Autodesk Fusion 360 part; units mm, degrees
(part 2 of 3)
sketch "locating_stops" plane through (0, 0, 7.25) normal (0, 0, 1) x (1, 0, 0) in component "drop_plate"
  line L0 (-82.375, -82.375) -> (-75.25, -82.375)
  line L1 (-75.25, -82.375) -> (-75.25, -80.125)
  line L2 (-75.25, -80.125) -> (-82.375, -80.125)
  line L3 (-82.375, -80.125) -> (-82.375, -82.375)
  line L4 (-82.375, -82.375) -> (-80.125, -82.375)
  line L5 (-80.125, -82.375) -> (-80.125, -75.25)
  line L6 (-80.125, -75.25) -> (-82.375, -75.25)
  line L7 (-82.375, -75.25) -> (-82.375, -82.375)
  line L8 (-82.375, -49.875) -> (-75.25, -49.875)
  line L9 (-75.25, -49.875) -> (-75.25, -47.625)
  line L10 (-75.25, -47.625) -> (-82.375, -47.625)
  line L11 (-82.375, -47.625) -> (-82.375, -49.875)
  line L12 (-82.375, -54.75) -> (-80.125, -54.75)
  line L13 (-80.125, -54.75) -> (-80.125, -42.75)
  line L14 (-80.125, -42.75) -> (-82.375, -42.75)
  line L15 (-82.375, -42.75) -> (-82.375, -54.75)
  line L16 (-82.375, -17.375) -> (-75.25, -17.375)
  line L17 (-75.25, -17.375) -> (-75.25, -15.125)
  line L18 (-75.25, -15.125) -> (-82.375, -15.125)
  line L19 (-82.375, -15.125) -> (-82.375, -17.375)
  line L20 (-82.375, -22.25) -> (-80.125, -22.25)
  line L21 (-80.125, -22.25) -> (-80.125, -10.25)
  line L22 (-80.125, -10.25) -> (-82.375, -10.25)
  line L23 (-82.375, -10.25) -> (-82.375, -22.25)
  line L24 (-82.375, 15.125) -> (-75.25, 15.125)
  line L25 (-75.25, 15.125) -> (-75.25, 17.375)
  line L26 (-75.25, 17.375) -> (-82.375, 17.375)
  line L27 (-82.375, 17.375) -> (-82.375, 15.125)
  line L28 (-82.375, 10.25) -> (-80.125, 10.25)
  line L29 (-80.125, 10.25) -> (-80.125, 22.25)
  line L30 (-80.125, 22.25) -> (-82.375, 22.25)
  line L31 (-82.375, 22.25) -> (-82.375, 10.25)
  line L32 (-82.375, 47.625) -> (-75.25, 47.625)
  line L33 (-75.25, 47.625) -> (-75.25, 49.875)
  line L34 (-75.25, 49.875) -> (-82.375, 49.875)
  line L35 (-82.375, 49.875) -> (-82.375, 47.625)
  line L36 (-82.375, 42.75) -> (-80.125, 42.75)
  line L37 (-80.125, 42.75) -> (-80.125, 54.75)
  line L38 (-80.125, 54.75) -> (-82.375, 54.75)
  line L39 (-82.375, 54.75) -> (-82.375, 42.75)
  line L40 (-82.375, 80.125) -> (-75.25, 80.125)
  line L41 (-75.25, 80.125) -> (-75.25, 82.375)
  line L42 (-75.25, 82.375) -> (-82.375, 82.375)
  line L43 (-82.375, 82.375) -> (-82.375, 80.125)
  line L44 (-82.375, 75.25) -> (-80.125, 75.25)
  line L45 (-80.125, 75.25) -> (-80.125, 82.375)
  line L46 (-80.125, 82.375) -> (-82.375, 82.375)
  line L47 (-82.375, 82.375) -> (-82.375, 75.25)
  line L48 (-54.75, -82.375) -> (-42.75, -82.375)
  line L49 (-42.75, -82.375) -> (-42.75, -80.125)
  line L50 (-42.75, -80.125) -> (-54.75, -80.125)
  line L51 (-54.75, -80.125) -> (-54.75, -82.375)
  line L52 (-49.875, -82.375) -> (-47.625, -82.375)
  line L53 (-47.625, -82.375) -> (-47.625, -75.25)
  line L54 (-47.625, -75.25) -> (-49.875, -75.25)
  line L55 (-49.875, -75.25) -> (-49.875, -82.375)
  line L56 (-54.75, -49.875) -> (-42.75, -49.875)
  line L57 (-42.75, -49.875) -> (-42.75, -47.625)
  line L58 (-42.75, -47.625) -> (-54.75, -47.625)
  line L59 (-54.75, -47.625) -> (-54.75, -49.875)
  line L60 (-49.875, -54.75) -> (-47.625, -54.75)
  line L61 (-47.625, -54.75) -> (-47.625, -42.75)
  line L62 (-47.625, -42.75) -> (-49.875, -42.75)
  line L63 (-49.875, -42.75) -> (-49.875, -54.75)
  line L64 (-54.75, -17.375) -> (-42.75, -17.375)
  line L65 (-42.75, -17.375) -> (-42.75, -15.125)
  line L66 (-42.75, -15.125) -> (-54.75, -15.125)
  line L67 (-54.75, -15.125) -> (-54.75, -17.375)
  line L68 (-49.875, -22.25) -> (-47.625, -22.25)
  line L69 (-47.625, -22.25) -> (-47.625, -10.25)
  line L70 (-47.625, -10.25) -> (-49.875, -10.25)
  line L71 (-49.875, -10.25) -> (-49.875, -22.25)
  line L72 (-54.75, 15.125) -> (-42.75, 15.125)
  line L73 (-42.75, 15.125) -> (-42.75, 17.375)
  line L74 (-42.75, 17.375) -> (-54.75, 17.375)
  line L75 (-54.75, 17.375) -> (-54.75, 15.125)
  line L76 (-49.875, 10.25) -> (-47.625, 10.25)
  line L77 (-47.625, 10.25) -> (-47.625, 22.25)
  line L78 (-47.625, 22.25) -> (-49.875, 22.25)
  line L79 (-49.875, 22.25) -> (-49.875, 10.25)
  line L80 (-54.75, 47.625) -> (-42.75, 47.625)
  line L81 (-42.75, 47.625) -> (-42.75, 49.875)
  line L82 (-42.75, 49.875) -> (-54.75, 49.875)
  line L83 (-54.75, 49.875) -> (-54.75, 47.625)
  line L84 (-49.875, 42.75) -> (-47.625, 42.75)
  line L85 (-47.625, 42.75) -> (-47.625, 54.75)
  line L86 (-47.625, 54.75) -> (-49.875, 54.75)
  line L87 (-49.875, 54.75) -> (-49.875, 42.75)
  line L88 (-54.75, 80.125) -> (-42.75, 80.125)
  line L89 (-42.75, 80.125) -> (-42.75, 82.375)
  line L90 (-42.75, 82.375) -> (-54.75, 82.375)
  line L91 (-54.75, 82.375) -> (-54.75, 80.125)
  line L92 (-49.875, 75.25) -> (-47.625, 75.25)
  line L93 (-47.625, 75.25) -> (-47.625, 82.375)
  line L94 (-47.625, 82.375) -> (-49.875, 82.375)
  line L95 (-49.875, 82.375) -> (-49.875, 75.25)
  line L96 (-22.25, -82.375) -> (-10.25, -82.375)
  line L97 (-10.25, -82.375) -> (-10.25, -80.125)
  line L98 (-10.25, -80.125) -> (-22.25, -80.125)
  line L99 (-22.25, -80.125) -> (-22.25, -82.375)
  line L100 (-17.375, -82.375) -> (-15.125, -82.375)
  line L101 (-15.125, -82.375) -> (-15.125, -75.25)
  line L102 (-15.125, -75.25) -> (-17.375, -75.25)
  line L103 (-17.375, -75.25) -> (-17.375, -82.375)
  line L104 (-22.25, -49.875) -> (-10.25, -49.875)
  line L105 (-10.25, -49.875) -> (-10.25, -47.625)
  line L106 (-10.25, -47.625) -> (-22.25, -47.625)
  line L107 (-22.25, -47.625) -> (-22.25, -49.875)
  line L108 (-17.375, -54.75) -> (-15.125, -54.75)
  line L109 (-15.125, -54.75) -> (-15.125, -42.75)
  line L110 (-15.125, -42.75) -> (-17.375, -42.75)
  line L111 (-17.375, -42.75) -> (-17.375, -54.75)
  line L112 (-22.25, -17.375) -> (-10.25, -17.375)
  line L113 (-10.25, -17.375) -> (-10.25, -15.125)
  line L114 (-10.25, -15.125) -> (-22.25, -15.125)
  line L115 (-22.25, -15.125) -> (-22.25, -17.375)
  line L116 (-17.375, -22.25) -> (-15.125, -22.25)
  line L117 (-15.125, -22.25) -> (-15.125, -10.25)
  line L118 (-15.125, -10.25) -> (-17.375, -10.25)
  line L119 (-17.375, -10.25) -> (-17.375, -22.25)
  line L120 (-22.25, 15.125) -> (-10.25, 15.125)
  line L121 (-10.25, 15.125) -> (-10.25, 17.375)
  line L122 (-10.25, 17.375) -> (-22.25, 17.375)
  line L123 (-22.25, 17.375) -> (-22.25, 15.125)
  line L124 (-17.375, 10.25) -> (-15.125, 10.25)
  line L125 (-15.125, 10.25) -> (-15.125, 22.25)
  line L126 (-15.125, 22.25) -> (-17.375, 22.25)
  line L127 (-17.375, 22.25) -> (-17.375, 10.25)
  line L128 (-22.25, 47.625) -> (-10.25, 47.625)
  line L129 (-10.25, 47.625) -> (-10.25, 49.875)
  line L130 (-10.25, 49.875) -> (-22.25, 49.875)
  line L131 (-22.25, 49.875) -> (-22.25, 47.625)
  line L132 (-17.375, 42.75) -> (-15.125, 42.75)
  line L133 (-15.125, 42.75) -> (-15.125, 54.75)
  line L134 (-15.125, 54.75) -> (-17.375, 54.75)
  line L135 (-17.375, 54.75) -> (-17.375, 42.75)
  line L136 (-22.25, 80.125) -> (-10.25, 80.125)
  line L137 (-10.25, 80.125) -> (-10.25, 82.375)
  line L138 (-10.25, 82.375) -> (-22.25, 82.375)
  line L139 (-22.25, 82.375) -> (-22.25, 80.125)
  line L140 (-17.375, 75.25) -> (-15.125, 75.25)
  line L141 (-15.125, 75.25) -> (-15.125, 82.375)
  line L142 (-15.125, 82.375) -> (-17.375, 82.375)
  line L143 (-17.375, 82.375) -> (-17.375, 75.25)
  line L144 (10.25, -82.375) -> (22.25, -82.375)
  line L145 (22.25, -82.375) -> (22.25, -80.125)
  line L146 (22.25, -80.125) -> (10.25, -80.125)
  line L147 (10.25, -80.125) -> (10.25, -82.375)
  line L148 (15.125, -82.375) -> (17.375, -82.375)
  line L149 (17.375, -82.375) -> (17.375, -75.25)
  line L150 (17.375, -75.25) -> (15.125, -75.25)
  line L151 (15.125, -75.25) -> (15.125, -82.375)
  line L152 (10.25, -49.875) -> (22.25, -49.875)
  line L153 (22.25, -49.875) -> (22.25, -47.625)
  line L154 (22.25, -47.625) -> (10.25, -47.625)
  line L155 (10.25, -47.625) -> (10.25, -49.875)
  line L156 (15.125, -54.75) -> (17.375, -54.75)
  line L157 (17.375, -54.75) -> (17.375, -42.75)
  line L158 (17.375, -42.75) -> (15.125, -42.75)
  line L159 (15.125, -42.75) -> (15.125, -54.75)
  line L160 (10.25, -17.375) -> (22.25, -17.375)
  line L161 (22.25, -17.375) -> (22.25, -15.125)
  line L162 (22.25, -15.125) -> (10.25, -15.125)
  line L163 (10.25, -15.125) -> (10.25, -17.375)
  line L164 (15.125, -22.25) -> (17.375, -22.25)
  line L165 (17.375, -22.25) -> (17.375, -10.25)
  line L166 (17.375, -10.25) -> (15.125, -10.25)
  line L167 (15.125, -10.25) -> (15.125, -22.25)
  line L168 (10.25, 15.125) -> (22.25, 15.125)
  line L169 (22.25, 15.125) -> (22.25, 17.375)
  line L170 (22.25, 17.375) -> (10.25, 17.375)
  line L171 (10.25, 17.375) -> (10.25, 15.125)
  line L172 (15.125, 10.25) -> (17.375, 10.25)
  line L173 (17.375, 10.25) -> (17.375, 22.25)
  line L174 (17.375, 22.25) -> (15.125, 22.25)
  line L175 (15.125, 22.25) -> (15.125, 10.25)
  line L176 (10.25, 47.625) -> (22.25, 47.625)
  line L177 (22.25, 47.625) -> (22.25, 49.875)
  line L178 (22.25, 49.875) -> (10.25, 49.875)
  line L179 (10.25, 49.875) -> (10.25, 47.625)
  line L180 (15.125, 42.75) -> (17.375, 42.75)
  line L181 (17.375, 42.75) -> (17.375, 54.75)
  line L182 (17.375, 54.75) -> (15.125, 54.75)
  line L183 (15.125, 54.75) -> (15.125, 42.75)
  line L184 (10.25, 80.125) -> (22.25, 80.125)
  line L185 (22.25, 80.125) -> (22.25, 82.375)
  line L186 (22.25, 82.375) -> (10.25, 82.375)
  line L187 (10.25, 82.375) -> (10.25, 80.125)
  line L188 (15.125, 75.25) -> (17.375, 75.25)
  line L189 (17.375, 75.25) -> (17.375, 82.375)
  line L190 (17.375, 82.375) -> (15.125, 82.375)
  line L191 (15.125, 82.375) -> (15.125, 75.25)
  line L192 (42.75, -82.375) -> (54.75, -82.375)
  line L193 (54.75, -82.375) -> (54.75, -80.125)
  line L194 (54.75, -80.125) -> (42.75, -80.125)
  line L195 (42.75, -80.125) -> (42.75, -82.375)
  line L196 (47.625, -82.375) -> (49.875, -82.375)
  line L197 (49.875, -82.375) -> (49.875, -75.25)
  line L198 (49.875, -75.25) -> (47.625, -75.25)
  line L199 (47.625, -75.25) -> (47.625, -82.375)
  line L200 (42.75, -49.875) -> (54.75, -49.875)
  line L201 (54.75, -49.875) -> (54.75, -47.625)
  line L202 (54.75, -47.625) -> (42.75, -47.625)
  line L203 (42.75, -47.625) -> (42.75, -49.875)
  line L204 (47.625, -54.75) -> (49.875, -54.75)
  line L205 (49.875, -54.75) -> (49.875, -42.75)
  line L206 (49.875, -42.75) -> (47.625, -42.75)
  line L207 (47.625, -42.75) -> (47.625, -54.75)
  line L208 (42.75, -17.375) -> (54.75, -17.375)
  line L209 (54.75, -17.375) -> (54.75, -15.125)
  line L210 (54.75, -15.125) -> (42.75, -15.125)
  line L211 (42.75, -15.125) -> (42.75, -17.375)
  line L212 (47.625, -22.25) -> (49.875, -22.25)
  line L213 (49.875, -22.25) -> (49.875, -10.25)
  line L214 (49.875, -10.25) -> (47.625, -10.25)
  line L215 (47.625, -10.25) -> (47.625, -22.25)
  line L216 (42.75, 15.125) -> (54.75, 15.125)
  line L217 (54.75, 15.125) -> (54.75, 17.375)
  line L218 (54.75, 17.375) -> (42.75, 17.375)
  line L219 (42.75, 17.375) -> (42.75, 15.125)
  line L220 (47.625, 10.25) -> (49.875, 10.25)
  line L221 (49.875, 10.25) -> (49.875, 22.25)
  line L222 (49.875, 22.25) -> (47.625, 22.25)
  line L223 (47.625, 22.25) -> (47.625, 10.25)
  line L224 (42.75, 47.625) -> (54.75, 47.625)
  line L225 (54.75, 47.625) -> (54.75, 49.875)
  line L226 (54.75, 49.875) -> (42.75, 49.875)
  line L227 (42.75, 49.875) -> (42.75, 47.625)
  line L228 (47.625, 42.75) -> (49.875, 42.75)
  line L229 (49.875, 42.75) -> (49.875, 54.75)
  line L230 (49.875, 54.75) -> (47.625, 54.75)
  line L231 (47.625, 54.75) -> (47.625, 42.75)
  line L232 (42.75, 80.125) -> (54.75, 80.125)
  line L233 (54.75, 80.125) -> (54.75, 82.375)
  line L234 (54.75, 82.375) -> (42.75, 82.375)
  line L235 (42.75, 82.375) -> (42.75, 80.125)
  line L236 (47.625, 75.25) -> (49.875, 75.25)
  line L237 (49.875, 75.25) -> (49.875, 82.375)
  line L238 (49.875, 82.375) -> (47.625, 82.375)
  line L239 (47.625, 82.375) -> (47.625, 75.25)
  line L240 (75.25, -82.375) -> (82.375, -82.375)
  line L241 (82.375, -82.375) -> (82.375, -80.125)
  line L242 (82.375, -80.125) -> (75.25, -80.125)
  line L243 (75.25, -80.125) -> (75.25, -82.375)
  line L244 (80.125, -82.375) -> (82.375, -82.375)
  line L245 (82.375, -82.375) -> (82.375, -75.25)
  line L246 (82.375, -75.25) -> (80.125, -75.25)
  line L247 (80.125, -75.25) -> (80.125, -82.375)
  line L248 (75.25, -49.875) -> (82.375, -49.875)
  line L249 (82.375, -49.875) -> (82.375, -47.625)
  line L250 (82.375, -47.625) -> (75.25, -47.625)
  line L251 (75.25, -47.625) -> (75.25, -49.875)
  line L252 (80.125, -54.75) -> (82.375, -54.75)
  line L253 (82.375, -54.75) -> (82.375, -42.75)
  line L254 (82.375, -42.75) -> (80.125, -42.75)
  line L255 (80.125, -42.75) -> (80.125, -54.75)
  line L256 (75.25, -17.375) -> (82.375, -17.375)
  line L257 (82.375, -17.375) -> (82.375, -15.125)
  line L258 (82.375, -15.125) -> (75.25, -15.125)
  line L259 (75.25, -15.125) -> (75.25, -17.375)
  line L260 (80.125, -22.25) -> (82.375, -22.25)
  line L261 (82.375, -22.25) -> (82.375, -10.25)
  line L262 (82.375, -10.25) -> (80.125, -10.25)
  line L263 (80.125, -10.25) -> (80.125, -22.25)
  line L264 (75.25, 15.125) -> (82.375, 15.125)
  line L265 (82.375, 15.125) -> (82.375, 17.375)
  line L266 (82.375, 17.375) -> (75.25, 17.375)
  line L267 (75.25, 17.375) -> (75.25, 15.125)
  line L268 (80.125, 10.25) -> (82.375, 10.25)
  line L269 (82.375, 10.25) -> (82.375, 22.25)
  line L270 (82.375, 22.25) -> (80.125, 22.25)
  line L271 (80.125, 22.25) -> (80.125, 10.25)
  line L272 (75.25, 47.625) -> (82.375, 47.625)
  line L273 (82.375, 47.625) -> (82.375, 49.875)
  line L274 (82.375, 49.875) -> (75.25, 49.875)
  line L275 (75.25, 49.875) -> (75.25, 47.625)
  line L276 (80.125, 42.75) -> (82.375, 42.75)
  line L277 (82.375, 42.75) -> (82.375, 54.75)
  line L278 (82.375, 54.75) -> (80.125, 54.75)
  line L279 (80.125, 54.75) -> (80.125, 42.75)
  line L280 (75.25, 80.125) -> (82.375, 80.125)
  line L281 (82.375, 80.125) -> (82.375, 82.375)
  line L282 (82.375, 82.375) -> (75.25, 82.375)
  line L283 (75.25, 82.375) -> (75.25, 80.125)
  line L284 (80.125, 75.25) -> (82.375, 75.25)
  line L285 (82.375, 75.25) -> (82.375, 82.375)
  line L286 (82.375, 82.375) -> (80.125, 82.375)
  line L287 (80.125, 82.375) -> (80.125, 75.25)
extrude "locating_stops (1)" add sketch "locating_stops" along normal blind 2.4 in component "drop_plate"
ref_plane "WorkPlane7" through (0, 0, 9.65) normal (0, 0, 1) x (1, 0, 0) in component "drop_plate"
sketch "orientation_post" plane through (0, 0, 9.65) normal (0, 0, 1) x (1, 0, 0) in component "drop_plate"
  line L0 (-82.375, -82.375) -> (-80.125, -82.375)
  line L1 (-80.125, -82.375) -> (-80.125, -80.125)
  line L2 (-80.125, -80.125) -> (-82.375, -80.125)
  line L3 (-82.375, -80.125) -> (-82.375, -82.375)
extrude "orientation_post (1)" add sketch "orientation_post" along normal blind 3 in component "drop_plate"
ref_plane "WorkPlane8" through (0, 0, 7.25) normal (0, 0, 1) x (1, 0, 0) in component "drop_plate"
sketch "scale_crosses" plane through (0, 0, 7.25) normal (0, 0, 1) x (1, 0, 0) in component "drop_plate"
  line L0 (-78, -76.3) -> (-74, -76.3)
  line L1 (-74, -76.3) -> (-74, -75.7)
  line L2 (-74, -75.7) -> (-78, -75.7)
  line L3 (-78, -75.7) -> (-78, -76.3)
  line L4 (-76.3, -78) -> (-75.7, -78)
  line L5 (-75.7, -78) -> (-75.7, -74)
  line L6 (-75.7, -74) -> (-76.3, -74)
  line L7 (-76.3, -74) -> (-76.3, -78)
  line L8 (-78, -54.3) -> (-74, -54.3)
  line L9 (-74, -54.3) -> (-74, -53.7)
  line L10 (-74, -53.7) -> (-78, -53.7)
  line L11 (-78, -53.7) -> (-78, -54.3)
  line L12 (-76.3, -56) -> (-75.7, -56)
  line L13 (-75.7, -56) -> (-75.7, -52)
  line L14 (-75.7, -52) -> (-76.3, -52)
  line L15 (-76.3, -52) -> (-76.3, -56)
  line L16 (-56, -76.3) -> (-52, -76.3)
  line L17 (-52, -76.3) -> (-52, -75.7)
  line L18 (-52, -75.7) -> (-56, -75.7)
  line L19 (-56, -75.7) -> (-56, -76.3)
  line L20 (-54.3, -78) -> (-53.7, -78)
  line L21 (-53.7, -78) -> (-53.7, -74)
  line L22 (-53.7, -74) -> (-54.3, -74)
  line L23 (-54.3, -74) -> (-54.3, -78)
  line L24 (-56, -54.3) -> (-52, -54.3)
  line L25 (-52, -54.3) -> (-52, -53.7)
  line L26 (-52, -53.7) -> (-56, -53.7)
  line L27 (-56, -53.7) -> (-56, -54.3)
  line L28 (-54.3, -56) -> (-53.7, -56)
  line L29 (-53.7, -56) -> (-53.7, -52)
  line L30 (-53.7, -52) -> (-54.3, -52)
  line L31 (-54.3, -52) -> (-54.3, -56)
  line L32 (-78, -43.8) -> (-74, -43.8)
  line L33 (-74, -43.8) -> (-74, -43.2)
  line L34 (-74, -43.2) -> (-78, -43.2)
  line L35 (-78, -43.2) -> (-78, -43.8)
  line L36 (-76.3, -45.5) -> (-75.7, -45.5)
  line L37 (-75.7, -45.5) -> (-75.7, -41.5)
  line L38 (-75.7, -41.5) -> (-76.3, -41.5)
  line L39 (-76.3, -41.5) -> (-76.3, -45.5)
  line L40 (-78, -21.8) -> (-74, -21.8)
  line L41 (-74, -21.8) -> (-74, -21.2)
  line L42 (-74, -21.2) -> (-78, -21.2)
  line L43 (-78, -21.2) -> (-78, -21.8)
  line L44 (-76.3, -23.5) -> (-75.7, -23.5)
  line L45 (-75.7, -23.5) -> (-75.7, -19.5)
  line L46 (-75.7, -19.5) -> (-76.3, -19.5)
  line L47 (-76.3, -19.5) -> (-76.3, -23.5)
  line L48 (-56, -43.8) -> (-52, -43.8)
  line L49 (-52, -43.8) -> (-52, -43.2)
  line L50 (-52, -43.2) -> (-56, -43.2)
  line L51 (-56, -43.2) -> (-56, -43.8)
  line L52 (-54.3, -45.5) -> (-53.7, -45.5)
  line L53 (-53.7, -45.5) -> (-53.7, -41.5)
  line L54 (-53.7, -41.5) -> (-54.3, -41.5)
  line L55 (-54.3, -41.5) -> (-54.3, -45.5)
  line L56 (-56, -21.8) -> (-52, -21.8)
  line L57 (-52, -21.8) -> (-52, -21.2)
  line L58 (-52, -21.2) -> (-56, -21.2)
  line L59 (-56, -21.2) -> (-56, -21.8)
  line L60 (-54.3, -23.5) -> (-53.7, -23.5)
  line L61 (-53.7, -23.5) -> (-53.7, -19.5)
  line L62 (-53.7, -19.5) -> (-54.3, -19.5)
  line L63 (-54.3, -19.5) -> (-54.3, -23.5)
  line L64 (-78, -11.3) -> (-74, -11.3)
  line L65 (-74, -11.3) -> (-74, -10.7)
  line L66 (-74, -10.7) -> (-78, -10.7)
  line L67 (-78, -10.7) -> (-78, -11.3)
  line L68 (-76.3, -13) -> (-75.7, -13)
  line L69 (-75.7, -13) -> (-75.7, -9)
  line L70 (-75.7, -9) -> (-76.3, -9)
  line L71 (-76.3, -9) -> (-76.3, -13)
  line L72 (-78, 10.7) -> (-74, 10.7)
  line L73 (-74, 10.7) -> (-74, 11.3)
  line L74 (-74, 11.3) -> (-78, 11.3)
  line L75 (-78, 11.3) -> (-78, 10.7)
  line L76 (-76.3, 9) -> (-75.7, 9)
  line L77 (-75.7, 9) -> (-75.7, 13)
  line L78 (-75.7, 13) -> (-76.3, 13)
  line L79 (-76.3, 13) -> (-76.3, 9)
  line L80 (-56, -11.3) -> (-52, -11.3)
  line L81 (-52, -11.3) -> (-52, -10.7)
  line L82 (-52, -10.7) -> (-56, -10.7)
  line L83 (-56, -10.7) -> (-56, -11.3)
  line L84 (-54.3, -13) -> (-53.7, -13)
  line L85 (-53.7, -13) -> (-53.7, -9)
  line L86 (-53.7, -9) -> (-54.3, -9)
  line L87 (-54.3, -9) -> (-54.3, -13)
  line L88 (-56, 10.7) -> (-52, 10.7)
  line L89 (-52, 10.7) -> (-52, 11.3)
  line L90 (-52, 11.3) -> (-56, 11.3)
  line L91 (-56, 11.3) -> (-56, 10.7)
  line L92 (-54.3, 9) -> (-53.7, 9)
  line L93 (-53.7, 9) -> (-53.7, 13)
  line L94 (-53.7, 13) -> (-54.3, 13)
  line L95 (-54.3, 13) -> (-54.3, 9)
  line L96 (-78, 21.2) -> (-74, 21.2)
  line L97 (-74, 21.2) -> (-74, 21.8)
  line L98 (-74, 21.8) -> (-78, 21.8)
  line L99 (-78, 21.8) -> (-78, 21.2)
  line L100 (-76.3, 19.5) -> (-75.7, 19.5)
  line L101 (-75.7, 19.5) -> (-75.7, 23.5)
  line L102 (-75.7, 23.5) -> (-76.3, 23.5)
  line L103 (-76.3, 23.5) -> (-76.3, 19.5)
  line L104 (-78, 43.2) -> (-74, 43.2)
  line L105 (-74, 43.2) -> (-74, 43.8)
  line L106 (-74, 43.8) -> (-78, 43.8)
  line L107 (-78, 43.8) -> (-78, 43.2)
  line L108 (-76.3, 41.5) -> (-75.7, 41.5)
  line L109 (-75.7, 41.5) -> (-75.7, 45.5)
  line L110 (-75.7, 45.5) -> (-76.3, 45.5)
  line L111 (-76.3, 45.5) -> (-76.3, 41.5)
  line L112 (-56, 21.2) -> (-52, 21.2)
  line L113 (-52, 21.2) -> (-52, 21.8)
  line L114 (-52, 21.8) -> (-56, 21.8)
  line L115 (-56, 21.8) -> (-56, 21.2)
  line L116 (-54.3, 19.5) -> (-53.7, 19.5)
  line L117 (-53.7, 19.5) -> (-53.7, 23.5)
  line L118 (-53.7, 23.5) -> (-54.3, 23.5)
  line L119 (-54.3, 23.5) -> (-54.3, 19.5)
  line L120 (-56, 43.2) -> (-52, 43.2)
  line L121 (-52, 43.2) -> (-52, 43.8)
  line L122 (-52, 43.8) -> (-56, 43.8)
  line L123 (-56, 43.8) -> (-56, 43.2)
  line L124 (-54.3, 41.5) -> (-53.7, 41.5)
  line L125 (-53.7, 41.5) -> (-53.7, 45.5)
  line L126 (-53.7, 45.5) -> (-54.3, 45.5)
  line L127 (-54.3, 45.5) -> (-54.3, 41.5)
  line L128 (-78, 53.7) -> (-74, 53.7)
  line L129 (-74, 53.7) -> (-74, 54.3)
  line L130 (-74, 54.3) -> (-78, 54.3)
  line L131 (-78, 54.3) -> (-78, 53.7)
  line L132 (-76.3, 52) -> (-75.7, 52)
  line L133 (-75.7, 52) -> (-75.7, 56)
  line L134 (-75.7, 56) -> (-76.3, 56)
  line L135 (-76.3, 56) -> (-76.3, 52)
  line L136 (-78, 75.7) -> (-74, 75.7)
  line L137 (-74, 75.7) -> (-74, 76.3)
  line L138 (-74, 76.3) -> (-78, 76.3)
  line L139 (-78, 76.3) -> (-78, 75.7)
  line L140 (-76.3, 74) -> (-75.7, 74)
  line L141 (-75.7, 74) -> (-75.7, 78)
  line L142 (-75.7, 78) -> (-76.3, 78)
  line L143 (-76.3, 78) -> (-76.3, 74)
  line L144 (-56, 53.7) -> (-52, 53.7)
  line L145 (-52, 53.7) -> (-52, 54.3)
  line L146 (-52, 54.3) -> (-56, 54.3)
  line L147 (-56, 54.3) -> (-56, 53.7)
  line L148 (-54.3, 52) -> (-53.7, 52)
  line L149 (-53.7, 52) -> (-53.7, 56)
  line L150 (-53.7, 56) -> (-54.3, 56)
  line L151 (-54.3, 56) -> (-54.3, 52)
  line L152 (-56, 75.7) -> (-52, 75.7)
  line L153 (-52, 75.7) -> (-52, 76.3)
  line L154 (-52, 76.3) -> (-56, 76.3)
  line L155 (-56, 76.3) -> (-56, 75.7)
  line L156 (-54.3, 74) -> (-53.7, 74)
  line L157 (-53.7, 74) -> (-53.7, 78)
  line L158 (-53.7, 78) -> (-54.3, 78)
  line L159 (-54.3, 78) -> (-54.3, 74)
  line L160 (-45.5, -76.3) -> (-41.5, -76.3)
  line L161 (-41.5, -76.3) -> (-41.5, -75.7)
  line L162 (-41.5, -75.7) -> (-45.5, -75.7)
  line L163 (-45.5, -75.7) -> (-45.5, -76.3)
  line L164 (-43.8, -78) -> (-43.2, -78)
  line L165 (-43.2, -78) -> (-43.2, -74)
  line L166 (-43.2, -74) -> (-43.8, -74)
  line L167 (-43.8, -74) -> (-43.8, -78)
  line L168 (-45.5, -54.3) -> (-41.5, -54.3)
  line L169 (-41.5, -54.3) -> (-41.5, -53.7)
  line L170 (-41.5, -53.7) -> (-45.5, -53.7)
  line L171 (-45.5, -53.7) -> (-45.5, -54.3)
  line L172 (-43.8, -56) -> (-43.2, -56)
  line L173 (-43.2, -56) -> (-43.2, -52)
  line L174 (-43.2, -52) -> (-43.8, -52)
  line L175 (-43.8, -52) -> (-43.8, -56)
  line L176 (-23.5, -76.3) -> (-19.5, -76.3)
  line L177 (-19.5, -76.3) -> (-19.5, -75.7)
  line L178 (-19.5, -75.7) -> (-23.5, -75.7)
  line L179 (-23.5, -75.7) -> (-23.5, -76.3)
  line L180 (-21.8, -78) -> (-21.2, -78)
  line L181 (-21.2, -78) -> (-21.2, -74)
  line L182 (-21.2, -74) -> (-21.8, -74)
  line L183 (-21.8, -74) -> (-21.8, -78)
  line L184 (-23.5, -54.3) -> (-19.5, -54.3)
  line L185 (-19.5, -54.3) -> (-19.5, -53.7)
  line L186 (-19.5, -53.7) -> (-23.5, -53.7)
  line L187 (-23.5, -53.7) -> (-23.5, -54.3)
  line L188 (-21.8, -56) -> (-21.2, -56)
  line L189 (-21.2, -56) -> (-21.2, -52)
  line L190 (-21.2, -52) -> (-21.8, -52)
  line L191 (-21.8, -52) -> (-21.8, -56)
  line L192 (-45.5, -43.8) -> (-41.5, -43.8)
  line L193 (-41.5, -43.8) -> (-41.5, -43.2)
  line L194 (-41.5, -43.2) -> (-45.5, -43.2)
  line L195 (-45.5, -43.2) -> (-45.5, -43.8)
  line L196 (-43.8, -45.5) -> (-43.2, -45.5)
  line L197 (-43.2, -45.5) -> (-43.2, -41.5)
  line L198 (-43.2, -41.5) -> (-43.8, -41.5)
  line L199 (-43.8, -41.5) -> (-43.8, -45.5)
  line L200 (-45.5, -21.8) -> (-41.5, -21.8)
  line L201 (-41.5, -21.8) -> (-41.5, -21.2)
  line L202 (-41.5, -21.2) -> (-45.5, -21.2)
  line L203 (-45.5, -21.2) -> (-45.5, -21.8)
  line L204 (-43.8, -23.5) -> (-43.2, -23.5)
  line L205 (-43.2, -23.5) -> (-43.2, -19.5)
  line L206 (-43.2, -19.5) -> (-43.8, -19.5)
  line L207 (-43.8, -19.5) -> (-43.8, -23.5)
  line L208 (-23.5, -43.8) -> (-19.5, -43.8)
  line L209 (-19.5, -43.8) -> (-19.5, -43.2)
  line L210 (-19.5, -43.2) -> (-23.5, -43.2)
  line L211 (-23.5, -43.2) -> (-23.5, -43.8)
  line L212 (-21.8, -45.5) -> (-21.2, -45.5)
  line L213 (-21.2, -45.5) -> (-21.2, -41.5)
  line L214 (-21.2, -41.5) -> (-21.8, -41.5)
  line L215 (-21.8, -41.5) -> (-21.8, -45.5)
  line L216 (-23.5, -21.8) -> (-19.5, -21.8)
  line L217 (-19.5, -21.8) -> (-19.5, -21.2)
  line L218 (-19.5, -21.2) -> (-23.5, -21.2)
  line L219 (-23.5, -21.2) -> (-23.5, -21.8)
  line L220 (-21.8, -23.5) -> (-21.2, -23.5)
  line L221 (-21.2, -23.5) -> (-21.2, -19.5)
  line L222 (-21.2, -19.5) -> (-21.8, -19.5)
  line L223 (-21.8, -19.5) -> (-21.8, -23.5)
  line L224 (-45.5, -11.3) -> (-41.5, -11.3)
  line L225 (-41.5, -11.3) -> (-41.5, -10.7)
  line L226 (-41.5, -10.7) -> (-45.5, -10.7)
  line L227 (-45.5, -10.7) -> (-45.5, -11.3)
  line L228 (-43.8, -13) -> (-43.2, -13)
  line L229 (-43.2, -13) -> (-43.2, -9)
  line L230 (-43.2, -9) -> (-43.8, -9)
  line L231 (-43.8, -9) -> (-43.8, -13)
  line L232 (-45.5, 10.7) -> (-41.5, 10.7)
  line L233 (-41.5, 10.7) -> (-41.5, 11.3)
  line L234 (-41.5, 11.3) -> (-45.5, 11.3)
  line L235 (-45.5, 11.3) -> (-45.5, 10.7)
  line L236 (-43.8, 9) -> (-43.2, 9)
  line L237 (-43.2, 9) -> (-43.2, 13)
  line L238 (-43.2, 13) -> (-43.8, 13)
  line L239 (-43.8, 13) -> (-43.8, 9)
  line L240 (-23.5, -11.3) -> (-19.5, -11.3)
  line L241 (-19.5, -11.3) -> (-19.5, -10.7)
  line L242 (-19.5, -10.7) -> (-23.5, -10.7)
  line L243 (-23.5, -10.7) -> (-23.5, -11.3)
  line L244 (-21.8, -13) -> (-21.2, -13)
  line L245 (-21.2, -13) -> (-21.2, -9)
  line L246 (-21.2, -9) -> (-21.8, -9)
  line L247 (-21.8, -9) -> (-21.8, -13)
  line L248 (-23.5, 10.7) -> (-19.5, 10.7)
  line L249 (-19.5, 10.7) -> (-19.5, 11.3)
  line L250 (-19.5, 11.3) -> (-23.5, 11.3)
  line L251 (-23.5, 11.3) -> (-23.5, 10.7)
  line L252 (-21.8, 9) -> (-21.2, 9)
  line L253 (-21.2, 9) -> (-21.2, 13)
  line L254 (-21.2, 13) -> (-21.8, 13)
  line L255 (-21.8, 13) -> (-21.8, 9)
  line L256 (-45.5, 21.2) -> (-41.5, 21.2)
  line L257 (-41.5, 21.2) -> (-41.5, 21.8)
  line L258 (-41.5, 21.8) -> (-45.5, 21.8)
  line L259 (-45.5, 21.8) -> (-45.5, 21.2)
  line L260 (-43.8, 19.5) -> (-43.2, 19.5)
  line L261 (-43.2, 19.5) -> (-43.2, 23.5)
  line L262 (-43.2, 23.5) -> (-43.8, 23.5)
  line L263 (-43.8, 23.5) -> (-43.8, 19.5)
  line L264 (-45.5, 43.2) -> (-41.5, 43.2)
  line L265 (-41.5, 43.2) -> (-41.5, 43.8)
  line L266 (-41.5, 43.8) -> (-45.5, 43.8)
  line L267 (-45.5, 43.8) -> (-45.5, 43.2)
  line L268 (-43.8, 41.5) -> (-43.2, 41.5)
  line L269 (-43.2, 41.5) -> (-43.2, 45.5)
  line L270 (-43.2, 45.5) -> (-43.8, 45.5)
  line L271 (-43.8, 45.5) -> (-43.8, 41.5)
  line L272 (-23.5, 21.2) -> (-19.5, 21.2)
  line L273 (-19.5, 21.2) -> (-19.5, 21.8)
  line L274 (-19.5, 21.8) -> (-23.5, 21.8)
  line L275 (-23.5, 21.8) -> (-23.5, 21.2)
  line L276 (-21.8, 19.5) -> (-21.2, 19.5)
  line L277 (-21.2, 19.5) -> (-21.2, 23.5)
  line L278 (-21.2, 23.5) -> (-21.8, 23.5)
  line L279 (-21.8, 23.5) -> (-21.8, 19.5)
  line L280 (-23.5, 43.2) -> (-19.5, 43.2)
  line L281 (-19.5, 43.2) -> (-19.5, 43.8)
  line L282 (-19.5, 43.8) -> (-23.5, 43.8)
  line L283 (-23.5, 43.8) -> (-23.5, 43.2)
  line L284 (-21.8, 41.5) -> (-21.2, 41.5)
  line L285 (-21.2, 41.5) -> (-21.2, 45.5)
  line L286 (-21.2, 45.5) -> (-21.8, 45.5)
  line L287 (-21.8, 45.5) -> (-21.8, 41.5)
  line L288 (-45.5, 53.7) -> (-41.5, 53.7)
  line L289 (-41.5, 53.7) -> (-41.5, 54.3)
  line L290 (-41.5, 54.3) -> (-45.5, 54.3)
  line L291 (-45.5, 54.3) -> (-45.5, 53.7)
  line L292 (-43.8, 52) -> (-43.2, 52)
  line L293 (-43.2, 52) -> (-43.2, 56)
  line L294 (-43.2, 56) -> (-43.8, 56)
  line L295 (-43.8, 56) -> (-43.8, 52)
  line L296 (-45.5, 75.7) -> (-41.5, 75.7)
  line L297 (-41.5, 75.7) -> (-41.5, 76.3)
  line L298 (-41.5, 76.3) -> (-45.5, 76.3)
  line L299 (-45.5, 76.3) -> (-45.5, 75.7)
  line L300 (-43.8, 74) -> (-43.2, 74)
  line L301 (-43.2, 74) -> (-43.2, 78)
  line L302 (-43.2, 78) -> (-43.8, 78)
  line L303 (-43.8, 78) -> (-43.8, 74)
  line L304 (-23.5, 53.7) -> (-19.5, 53.7)
  line L305 (-19.5, 53.7) -> (-19.5, 54.3)
  line L306 (-19.5, 54.3) -> (-23.5, 54.3)
  line L307 (-23.5, 54.3) -> (-23.5, 53.7)
  line L308 (-21.8, 52) -> (-21.2, 52)
  line L309 (-21.2, 52) -> (-21.2, 56)
  line L310 (-21.2, 56) -> (-21.8, 56)
  line L311 (-21.8, 56) -> (-21.8, 52)
  line L312 (-23.5, 75.7) -> (-19.5, 75.7)
  line L313 (-19.5, 75.7) -> (-19.5, 76.3)
  line L314 (-19.5, 76.3) -> (-23.5, 76.3)
  line L315 (-23.5, 76.3) -> (-23.5, 75.7)
  line L316 (-21.8, 74) -> (-21.2, 74)
  line L317 (-21.2, 74) -> (-21.2, 78)
  line L318 (-21.2, 78) -> (-21.8, 78)
  line L319 (-21.8, 78) -> (-21.8, 74)
  line L320 (-13, -76.3) -> (-9, -76.3)
  line L321 (-9, -76.3) -> (-9, -75.7)
  line L322 (-9, -75.7) -> (-13, -75.7)
  line L323 (-13, -75.7) -> (-13, -76.3)
  line L324 (-11.3, -78) -> (-10.7, -78)
  line L325 (-10.7, -78) -> (-10.7, -74)
  line L326 (-10.7, -74) -> (-11.3, -74)
  line L327 (-11.3, -74) -> (-11.3, -78)
  line L328 (-13, -54.3) -> (-9, -54.3)
  line L329 (-9, -54.3) -> (-9, -53.7)
  line L330 (-9, -53.7) -> (-13, -53.7)
  line L331 (-13, -53.7) -> (-13, -54.3)
  line L332 (-11.3, -56) -> (-10.7, -56)
  line L333 (-10.7, -56) -> (-10.7, -52)
  line L334 (-10.7, -52) -> (-11.3, -52)
  line L335 (-11.3, -52) -> (-11.3, -56)
  line L336 (9, -76.3) -> (13, -76.3)
  line L337 (13, -76.3) -> (13, -75.7)
  line L338 (13, -75.7) -> (9, -75.7)
  line L339 (9, -75.7) -> (9, -76.3)
  line L340 (10.7, -78) -> (11.3, -78)
  line L341 (11.3, -78) -> (11.3, -74)
  line L342 (11.3, -74) -> (10.7, -74)
  line L343 (10.7, -74) -> (10.7, -78)
  line L344 (9, -54.3) -> (13, -54.3)
  line L345 (13, -54.3) -> (13, -53.7)
  line L346 (13, -53.7) -> (9, -53.7)
  line L347 (9, -53.7) -> (9, -54.3)
  line L348 (10.7, -56) -> (11.3, -56)
  line L349 (11.3, -56) -> (11.3, -52)
  line L350 (11.3, -52) -> (10.7, -52)
  line L351 (10.7, -52) -> (10.7, -56)
  line L352 (-13, -43.8) -> (-9, -43.8)
  line L353 (-9, -43.8) -> (-9, -43.2)
  line L354 (-9, -43.2) -> (-13, -43.2)
  line L355 (-13, -43.2) -> (-13, -43.8)
  line L356 (-11.3, -45.5) -> (-10.7, -45.5)
  line L357 (-10.7, -45.5) -> (-10.7, -41.5)
  line L358 (-10.7, -41.5) -> (-11.3, -41.5)
  line L359 (-11.3, -41.5) -> (-11.3, -45.5)
  line L360 (-13, -21.8) -> (-9, -21.8)
  line L361 (-9, -21.8) -> (-9, -21.2)
  line L362 (-9, -21.2) -> (-13, -21.2)
  line L363 (-13, -21.2) -> (-13, -21.8)
  line L364 (-11.3, -23.5) -> (-10.7, -23.5)
  line L365 (-10.7, -23.5) -> (-10.7, -19.5)
  line L366 (-10.7, -19.5) -> (-11.3, -19.5)
  line L367 (-11.3, -19.5) -> (-11.3, -23.5)
  line L368 (9, -43.8) -> (13, -43.8)
  line L369 (13, -43.8) -> (13, -43.2)
  line L370 (13, -43.2) -> (9, -43.2)
  line L371 (9, -43.2) -> (9, -43.8)
  line L372 (10.7, -45.5) -> (11.3, -45.5)
  line L373 (11.3, -45.5) -> (11.3, -41.5)
  line L374 (11.3, -41.5) -> (10.7, -41.5)
  line L375 (10.7, -41.5) -> (10.7, -45.5)
  line L376 (9, -21.8) -> (13, -21.8)
  line L377 (13, -21.8) -> (13, -21.2)
  line L378 (13, -21.2) -> (9, -21.2)
  line L379 (9, -21.2) -> (9, -21.8)
  line L380 (10.7, -23.5) -> (11.3, -23.5)
  line L381 (11.3, -23.5) -> (11.3, -19.5)
  line L382 (11.3, -19.5) -> (10.7, -19.5)
  line L383 (10.7, -19.5) -> (10.7, -23.5)
  line L384 (-13, -11.3) -> (-9, -11.3)
  line L385 (-9, -11.3) -> (-9, -10.7)
  line L386 (-9, -10.7) -> (-13, -10.7)
  line L387 (-13, -10.7) -> (-13, -11.3)
  line L388 (-11.3, -13) -> (-10.7, -13)
  line L389 (-10.7, -13) -> (-10.7, -9)
  line L390 (-10.7, -9) -> (-11.3, -9)
  line L391 (-11.3, -9) -> (-11.3, -13)
  line L392 (-13, 10.7) -> (-9, 10.7)
  line L393 (-9, 10.7) -> (-9, 11.3)
  line L394 (-9, 11.3) -> (-13, 11.3)
  line L395 (-13, 11.3) -> (-13, 10.7)
  line L396 (-11.3, 9) -> (-10.7, 9)
  line L397 (-10.7, 9) -> (-10.7, 13)
  line L398 (-10.7, 13) -> (-11.3, 13)
  line L399 (-11.3, 13) -> (-11.3, 9)
  line L400 (9, -11.3) -> (13, -11.3)
  line L401 (13, -11.3) -> (13, -10.7)
  line L402 (13, -10.7) -> (9, -10.7)
  line L403 (9, -10.7) -> (9, -11.3)
  line L404 (10.7, -13) -> (11.3, -13)
  line L405 (11.3, -13) -> (11.3, -9)
  line L406 (11.3, -9) -> (10.7, -9)
  line L407 (10.7, -9) -> (10.7, -13)
  line L408 (9, 10.7) -> (13, 10.7)
  line L409 (13, 10.7) -> (13, 11.3)
  line L410 (13, 11.3) -> (9, 11.3)
  line L411 (9, 11.3) -> (9, 10.7)
  line L412 (10.7, 9) -> (11.3, 9)
  line L413 (11.3, 9) -> (11.3, 13)
  line L414 (11.3, 13) -> (10.7, 13)
  line L415 (10.7, 13) -> (10.7, 9)
  line L416 (-13, 21.2) -> (-9, 21.2)
  line L417 (-9, 21.2) -> (-9, 21.8)
  line L418 (-9, 21.8) -> (-13, 21.8)
  line L419 (-13, 21.8) -> (-13, 21.2)
  line L420 (-11.3, 19.5) -> (-10.7, 19.5)
  line L421 (-10.7, 19.5) -> (-10.7, 23.5)
  line L422 (-10.7, 23.5) -> (-11.3, 23.5)
  line L423 (-11.3, 23.5) -> (-11.3, 19.5)
  line L424 (-13, 43.2) -> (-9, 43.2)
  line L425 (-9, 43.2) -> (-9, 43.8)
  line L426 (-9, 43.8) -> (-13, 43.8)
  line L427 (-13, 43.8) -> (-13, 43.2)
  line L428 (-11.3, 41.5) -> (-10.7, 41.5)
  line L429 (-10.7, 41.5) -> (-10.7, 45.5)
  line L430 (-10.7, 45.5) -> (-11.3, 45.5)
  line L431 (-11.3, 45.5) -> (-11.3, 41.5)
  line L432 (9, 21.2) -> (13, 21.2)
  line L433 (13, 21.2) -> (13, 21.8)
  line L434 (13, 21.8) -> (9, 21.8)
  line L435 (9, 21.8) -> (9, 21.2)
  line L436 (10.7, 19.5) -> (11.3, 19.5)
  line L437 (11.3, 19.5) -> (11.3, 23.5)
  line L438 (11.3, 23.5) -> (10.7, 23.5)
  line L439 (10.7, 23.5) -> (10.7, 19.5)
  line L440 (9, 43.2) -> (13, 43.2)
  line L441 (13, 43.2) -> (13, 43.8)
  line L442 (13, 43.8) -> (9, 43.8)
  line L443 (9, 43.8) -> (9, 43.2)
  line L444 (10.7, 41.5) -> (11.3, 41.5)
  line L445 (11.3, 41.5) -> (11.3, 45.5)
  line L446 (11.3, 45.5) -> (10.7, 45.5)
  line L447 (10.7, 45.5) -> (10.7, 41.5)
  line L448 (-13, 53.7) -> (-9, 53.7)
  line L449 (-9, 53.7) -> (-9, 54.3)
  line L450 (-9, 54.3) -> (-13, 54.3)
  line L451 (-13, 54.3) -> (-13, 53.7)
  line L452 (-11.3, 52) -> (-10.7, 52)
  line L453 (-10.7, 52) -> (-10.7, 56)
  line L454 (-10.7, 56) -> (-11.3, 56)
  line L455 (-11.3, 56) -> (-11.3, 52)
  line L456 (-13, 75.7) -> (-9, 75.7)
  line L457 (-9, 75.7) -> (-9, 76.3)
  line L458 (-9, 76.3) -> (-13, 76.3)
  line L459 (-13, 76.3) -> (-13, 75.7)
  line L460 (-11.3, 74) -> (-10.7, 74)
  line L461 (-10.7, 74) -> (-10.7, 78)
  line L462 (-10.7, 78) -> (-11.3, 78)
  line L463 (-11.3, 78) -> (-11.3, 74)
  line L464 (9, 53.7) -> (13, 53.7)
  line L465 (13, 53.7) -> (13, 54.3)
  line L466 (13, 54.3) -> (9, 54.3)
  line L467 (9, 54.3) -> (9, 53.7)
  line L468 (10.7, 52) -> (11.3, 52)
  line L469 (11.3, 52) -> (11.3, 56)
  line L470 (11.3, 56) -> (10.7, 56)
  line L471 (10.7, 56) -> (10.7, 52)
  line L472 (9, 75.7) -> (13, 75.7)
  line L473 (13, 75.7) -> (13, 76.3)
  line L474 (13, 76.3) -> (9, 76.3)
  line L475 (9, 76.3) -> (9, 75.7)
  line L476 (10.7, 74) -> (11.3, 74)
  line L477 (11.3, 74) -> (11.3, 78)
  line L478 (11.3, 78) -> (10.7, 78)
  line L479 (10.7, 78) -> (10.7, 74)
  line L480 (19.5, -76.3) -> (23.5, -76.3)
  line L481 (23.5, -76.3) -> (23.5, -75.7)
  line L482 (23.5, -75.7) -> (19.5, -75.7)
  line L483 (19.5, -75.7) -> (19.5, -76.3)
  line L484 (21.2, -78) -> (21.8, -78)
  line L485 (21.8, -78) -> (21.8, -74)
  line L486 (21.8, -74) -> (21.2, -74)
  line L487 (21.2, -74) -> (21.2, -78)
  line L488 (19.5, -54.3) -> (23.5, -54.3)
  line L489 (23.5, -54.3) -> (23.5, -53.7)
  line L490 (23.5, -53.7) -> (19.5, -53.7)
  line L491 (19.5, -53.7) -> (19.5, -54.3)
  line L492 (21.2, -56) -> (21.8, -56)
  line L493 (21.8, -56) -> (21.8, -52)
  line L494 (21.8, -52) -> (21.2, -52)
  line L495 (21.2, -52) -> (21.2, -56)
  line L496 (41.5, -76.3) -> (45.5, -76.3)
  line L497 (45.5, -76.3) -> (45.5, -75.7)
  line L498 (45.5, -75.7) -> (41.5, -75.7)
  line L499 (41.5, -75.7) -> (41.5, -76.3)
  line L500 (43.2, -78) -> (43.8, -78)
  line L501 (43.8, -78) -> (43.8, -74)
  line L502 (43.8, -74) -> (43.2, -74)
  line L503 (43.2, -74) -> (43.2, -78)
  line L504 (41.5, -54.3) -> (45.5, -54.3)
  line L505 (45.5, -54.3) -> (45.5, -53.7)
  line L506 (45.5, -53.7) -> (41.5, -53.7)
  line L507 (41.5, -53.7) -> (41.5, -54.3)
  line L508 (43.2, -56) -> (43.8, -56)
  line L509 (43.8, -56) -> (43.8, -52)
  line L510 (43.8, -52) -> (43.2, -52)
  line L511 (43.2, -52) -> (43.2, -56)
  line L512 (19.5, -43.8) -> (23.5, -43.8)
  line L513 (23.5, -43.8) -> (23.5, -43.2)
  line L514 (23.5, -43.2) -> (19.5, -43.2)
  line L515 (19.5, -43.2) -> (19.5, -43.8)
  line L516 (21.2, -45.5) -> (21.8, -45.5)
  line L517 (21.8, -45.5) -> (21.8, -41.5)
  line L518 (21.8, -41.5) -> (21.2, -41.5)
  line L519 (21.2, -41.5) -> (21.2, -45.5)
  line L520 (19.5, -21.8) -> (23.5, -21.8)
  line L521 (23.5, -21.8) -> (23.5, -21.2)
  line L522 (23.5, -21.2) -> (19.5, -21.2)
  line L523 (19.5, -21.2) -> (19.5, -21.8)
  line L524 (21.2, -23.5) -> (21.8, -23.5)
  line L525 (21.8, -23.5) -> (21.8, -19.5)
  line L526 (21.8, -19.5) -> (21.2, -19.5)
  line L527 (21.2, -19.5) -> (21.2, -23.5)
  line L528 (41.5, -43.8) -> (45.5, -43.8)
  line L529 (45.5, -43.8) -> (45.5, -43.2)
  line L530 (45.5, -43.2) -> (41.5, -43.2)
  line L531 (41.5, -43.2) -> (41.5, -43.8)
  line L532 (43.2, -45.5) -> (43.8, -45.5)
  line L533 (43.8, -45.5) -> (43.8, -41.5)
  line L534 (43.8, -41.5) -> (43.2, -41.5)
  line L535 (43.2, -41.5) -> (43.2, -45.5)
  line L536 (41.5, -21.8) -> (45.5, -21.8)
  line L537 (45.5, -21.8) -> (45.5, -21.2)
  line L538 (45.5, -21.2) -> (41.5, -21.2)
  line L539 (41.5, -21.2) -> (41.5, -21.8)
  line L540 (43.2, -23.5) -> (43.8, -23.5)
  line L541 (43.8, -23.5) -> (43.8, -19.5)
  line L542 (43.8, -19.5) -> (43.2, -19.5)
  line L543 (43.2, -19.5) -> (43.2, -23.5)
  line L544 (19.5, -11.3) -> (23.5, -11.3)
  line L545 (23.5, -11.3) -> (23.5, -10.7)
  line L546 (23.5, -10.7) -> (19.5, -10.7)
  line L547 (19.5, -10.7) -> (19.5, -11.3)
  line L548 (21.2, -13) -> (21.8, -13)
  line L549 (21.8, -13) -> (21.8, -9)
  line L550 (21.8, -9) -> (21.2, -9)
  line L551 (21.2, -9) -> (21.2, -13)
  line L552 (19.5, 10.7) -> (23.5, 10.7)
  line L553 (23.5, 10.7) -> (23.5, 11.3)
  line L554 (23.5, 11.3) -> (19.5, 11.3)
  line L555 (19.5, 11.3) -> (19.5, 10.7)
  line L556 (21.2, 9) -> (21.8, 9)
  line L557 (21.8, 9) -> (21.8, 13)
  line L558 (21.8, 13) -> (21.2, 13)
  line L559 (21.2, 13) -> (21.2, 9)
  line L560 (41.5, -11.3) -> (45.5, -11.3)
  line L561 (45.5, -11.3) -> (45.5, -10.7)
  line L562 (45.5, -10.7) -> (41.5, -10.7)
  line L563 (41.5, -10.7) -> (41.5, -11.3)
  line L564 (43.2, -13) -> (43.8, -13)
  line L565 (43.8, -13) -> (43.8, -9)
  line L566 (43.8, -9) -> (43.2, -9)
  line L567 (43.2, -9) -> (43.2, -13)
  line L568 (41.5, 10.7) -> (45.5, 10.7)
  line L569 (45.5, 10.7) -> (45.5, 11.3)
  line L570 (45.5, 11.3) -> (41.5, 11.3)
  line L571 (41.5, 11.3) -> (41.5, 10.7)
  line L572 (43.2, 9) -> (43.8, 9)
  line L573 (43.8, 9) -> (43.8, 13)
  line L574 (43.8, 13) -> (43.2, 13)
  line L575 (43.2, 13) -> (43.2, 9)
  line L576 (19.5, 21.2) -> (23.5, 21.2)
  line L577 (23.5, 21.2) -> (23.5, 21.8)
  line L578 (23.5, 21.8) -> (19.5, 21.8)
  line L579 (19.5, 21.8) -> (19.5, 21.2)
  line L580 (21.2, 19.5) -> (21.8, 19.5)
  line L581 (21.8, 19.5) -> (21.8, 23.5)
  line L582 (21.8, 23.5) -> (21.2, 23.5)
  line L583 (21.2, 23.5) -> (21.2, 19.5)
  line L584 (19.5, 43.2) -> (23.5, 43.2)
  line L585 (23.5, 43.2) -> (23.5, 43.8)
  line L586 (23.5, 43.8) -> (19.5, 43.8)
  line L587 (19.5, 43.8) -> (19.5, 43.2)
  line L588 (21.2, 41.5) -> (21.8, 41.5)
  line L589 (21.8, 41.5) -> (21.8, 45.5)
  line L590 (21.8, 45.5) -> (21.2, 45.5)
  line L591 (21.2, 45.5) -> (21.2, 41.5)
  line L592 (41.5, 21.2) -> (45.5, 21.2)
  line L593 (45.5, 21.2) -> (45.5, 21.8)
  line L594 (45.5, 21.8) -> (41.5, 21.8)
  line L595 (41.5, 21.8) -> (41.5, 21.2)
  line L596 (43.2, 19.5) -> (43.8, 19.5)
  line L597 (43.8, 19.5) -> (43.8, 23.5)
  line L598 (43.8, 23.5) -> (43.2, 23.5)
  line L599 (43.2, 23.5) -> (43.2, 19.5)
  line L600 (41.5, 43.2) -> (45.5, 43.2)
  line L601 (45.5, 43.2) -> (45.5, 43.8)
  line L602 (45.5, 43.8) -> (41.5, 43.8)
  line L603 (41.5, 43.8) -> (41.5, 43.2)
  line L604 (43.2, 41.5) -> (43.8, 41.5)
  line L605 (43.8, 41.5) -> (43.8, 45.5)
  line L606 (43.8, 45.5) -> (43.2, 45.5)
  line L607 (43.2, 45.5) -> (43.2, 41.5)
  line L608 (19.5, 53.7) -> (23.5, 53.7)
  line L609 (23.5, 53.7) -> (23.5, 54.3)
  line L610 (23.5, 54.3) -> (19.5, 54.3)
  line L611 (19.5, 54.3) -> (19.5, 53.7)
  line L612 (21.2, 52) -> (21.8, 52)
  line L613 (21.8, 52) -> (21.8, 56)
  line L614 (21.8, 56) -> (21.2, 56)
  line L615 (21.2, 56) -> (21.2, 52)
  line L616 (19.5, 75.7) -> (23.5, 75.7)
  line L617 (23.5, 75.7) -> (23.5, 76.3)
  line L618 (23.5, 76.3) -> (19.5, 76.3)
  line L619 (19.5, 76.3) -> (19.5, 75.7)
  line L620 (21.2, 74) -> (21.8, 74)
  line L621 (21.8, 74) -> (21.8, 78)
  line L622 (21.8, 78) -> (21.2, 78)
  line L623 (21.2, 78) -> (21.2, 74)
  line L624 (41.5, 53.7) -> (45.5, 53.7)
  line L625 (45.5, 53.7) -> (45.5, 54.3)
  line L626 (45.5, 54.3) -> (41.5, 54.3)
  line L627 (41.5, 54.3) -> (41.5, 53.7)
  line L628 (43.2, 52) -> (43.8, 52)
  line L629 (43.8, 52) -> (43.8, 56)
  line L630 (43.8, 56) -> (43.2, 56)
  line L631 (43.2, 56) -> (43.2, 52)
  line L632 (41.5, 75.7) -> (45.5, 75.7)
  line L633 (45.5, 75.7) -> (45.5, 76.3)
  line L634 (45.5, 76.3) -> (41.5, 76.3)
  line L635 (41.5, 76.3) -> (41.5, 75.7)
  line L636 (43.2, 74) -> (43.8, 74)
  line L637 (43.8, 74) -> (43.8, 78)
  line L638 (43.8, 78) -> (43.2, 78)
  line L639 (43.2, 78) -> (43.2, 74)
  line L640 (52, -76.3) -> (56, -76.3)
  line L641 (56, -76.3) -> (56, -75.7)
  line L642 (56, -75.7) -> (52, -75.7)
  line L643 (52, -75.7) -> (52, -76.3)
  line L644 (53.7, -78) -> (54.3, -78)
  line L645 (54.3, -78) -> (54.3, -74)
  line L646 (54.3, -74) -> (53.7, -74)
  line L647 (53.7, -74) -> (53.7, -78)
  line L648 (52, -54.3) -> (56, -54.3)
  line L649 (56, -54.3) -> (56, -53.7)
  line L650 (56, -53.7) -> (52, -53.7)
  line L651 (52, -53.7) -> (52, -54.3)
  line L652 (53.7, -56) -> (54.3, -56)
  line L653 (54.3, -56) -> (54.3, -52)
  line L654 (54.3, -52) -> (53.7, -52)
  line L655 (53.7, -52) -> (53.7, -56)
  line L656 (74, -76.3) -> (78, -76.3)
  line L657 (78, -76.3) -> (78, -75.7)
  line L658 (78, -75.7) -> (74, -75.7)
  line L659 (74, -75.7) -> (74, -76.3)
  line L660 (75.7, -78) -> (76.3, -78)
  line L661 (76.3, -78) -> (76.3, -74)
  line L662 (76.3, -74) -> (75.7, -74)
  line L663 (75.7, -74) -> (75.7, -78)
  line L664 (74, -54.3) -> (78, -54.3)
  line L665 (78, -54.3) -> (78, -53.7)
  line L666 (78, -53.7) -> (74, -53.7)
  line L667 (74, -53.7) -> (74, -54.3)
  line L668 (75.7, -56) -> (76.3, -56)
  line L669 (76.3, -56) -> (76.3, -52)
  line L670 (76.3, -52) -> (75.7, -52)
  line L671 (75.7, -52) -> (75.7, -56)
  line L672 (52, -43.8) -> (56, -43.8)
  line L673 (56, -43.8) -> (56, -43.2)
  line L674 (56, -43.2) -> (52, -43.2)
  line L675 (52, -43.2) -> (52, -43.8)
  line L676 (53.7, -45.5) -> (54.3, -45.5)
  line L677 (54.3, -45.5) -> (54.3, -41.5)
  line L678 (54.3, -41.5) -> (53.7, -41.5)
  line L679 (53.7, -41.5) -> (53.7, -45.5)
  line L680 (52, -21.8) -> (56, -21.8)
  line L681 (56, -21.8) -> (56, -21.2)
  line L682 (56, -21.2) -> (52, -21.2)
  line L683 (52, -21.2) -> (52, -21.8)
  line L684 (53.7, -23.5) -> (54.3, -23.5)
  line L685 (54.3, -23.5) -> (54.3, -19.5)
  line L686 (54.3, -19.5) -> (53.7, -19.5)
  line L687 (53.7, -19.5) -> (53.7, -23.5)
  line L688 (74, -43.8) -> (78, -43.8)
  line L689 (78, -43.8) -> (78, -43.2)
  line L690 (78, -43.2) -> (74, -43.2)
  line L691 (74, -43.2) -> (74, -43.8)
  line L692 (75.7, -45.5) -> (76.3, -45.5)
  line L693 (76.3, -45.5) -> (76.3, -41.5)
  line L694 (76.3, -41.5) -> (75.7, -41.5)
  line L695 (75.7, -41.5) -> (75.7, -45.5)
  line L696 (74, -21.8) -> (78, -21.8)
  line L697 (78, -21.8) -> (78, -21.2)
  line L698 (78, -21.2) -> (74, -21.2)
  line L699 (74, -21.2) -> (74, -21.8)
  line L700 (75.7, -23.5) -> (76.3, -23.5)
  line L701 (76.3, -23.5) -> (76.3, -19.5)
  line L702 (76.3, -19.5) -> (75.7, -19.5)
  line L703 (75.7, -19.5) -> (75.7, -23.5)
  line L704 (52, -11.3) -> (56, -11.3)
  line L705 (56, -11.3) -> (56, -10.7)
  line L706 (56, -10.7) -> (52, -10.7)
  line L707 (52, -10.7) -> (52, -11.3)
  line L708 (53.7, -13) -> (54.3, -13)
  line L709 (54.3, -13) -> (54.3, -9)
  line L710 (54.3, -9) -> (53.7, -9)
  line L711 (53.7, -9) -> (53.7, -13)
  line L712 (52, 10.7) -> (56, 10.7)
  line L713 (56, 10.7) -> (56, 11.3)
  line L714 (56, 11.3) -> (52, 11.3)
  line L715 (52, 11.3) -> (52, 10.7)
  line L716 (53.7, 9) -> (54.3, 9)
  line L717 (54.3, 9) -> (54.3, 13)
  line L718 (54.3, 13) -> (53.7, 13)
  line L719 (53.7, 13) -> (53.7, 9)
  line L720 (74, -11.3) -> (78, -11.3)
  line L721 (78, -11.3) -> (78, -10.7)
  line L722 (78, -10.7) -> (74, -10.7)
  line L723 (74, -10.7) -> (74, -11.3)
  line L724 (75.7, -13) -> (76.3, -13)
  line L725 (76.3, -13) -> (76.3, -9)
  line L726 (76.3, -9) -> (75.7, -9)
  line L727 (75.7, -9) -> (75.7, -13)
  line L728 (74, 10.7) -> (78, 10.7)
  line L729 (78, 10.7) -> (78, 11.3)
  line L730 (78, 11.3) -> (74, 11.3)
  line L731 (74, 11.3) -> (74, 10.7)
  line L732 (75.7, 9) -> (76.3, 9)
  line L733 (76.3, 9) -> (76.3, 13)
  line L734 (76.3, 13) -> (75.7, 13)
  line L735 (75.7, 13) -> (75.7, 9)
  line L736 (52, 21.2) -> (56, 21.2)
  line L737 (56, 21.2) -> (56, 21.8)
  line L738 (56, 21.8) -> (52, 21.8)
  line L739 (52, 21.8) -> (52, 21.2)
  line L740 (53.7, 19.5) -> (54.3, 19.5)
  line L741 (54.3, 19.5) -> (54.3, 23.5)
  line L742 (54.3, 23.5) -> (53.7, 23.5)
  line L743 (53.7, 23.5) -> (53.7, 19.5)
  line L744 (52, 43.2) -> (56, 43.2)
  line L745 (56, 43.2) -> (56, 43.8)
  line L746 (56, 43.8) -> (52, 43.8)
  line L747 (52, 43.8) -> (52, 43.2)
  line L748 (53.7, 41.5) -> (54.3, 41.5)
  line L749 (54.3, 41.5) -> (54.3, 45.5)
  line L750 (54.3, 45.5) -> (53.7, 45.5)
  line L751 (53.7, 45.5) -> (53.7, 41.5)
  line L752 (74, 21.2) -> (78, 21.2)
  line L753 (78, 21.2) -> (78, 21.8)
  line L754 (78, 21.8) -> (74, 21.8)
  line L755 (74, 21.8) -> (74, 21.2)
  line L756 (75.7, 19.5) -> (76.3, 19.5)
  line L757 (76.3, 19.5) -> (76.3, 23.5)
  line L758 (76.3, 23.5) -> (75.7, 23.5)
  line L759 (75.7, 23.5) -> (75.7, 19.5)
  line L760 (74, 43.2) -> (78, 43.2)
  line L761 (78, 43.2) -> (78, 43.8)
  line L762 (78, 43.8) -> (74, 43.8)
  line L763 (74, 43.8) -> (74, 43.2)
  line L764 (75.7, 41.5) -> (76.3, 41.5)
  line L765 (76.3, 41.5) -> (76.3, 45.5)
  line L766 (76.3, 45.5) -> (75.7, 45.5)
  line L767 (75.7, 45.5) -> (75.7, 41.5)
  line L768 (52, 53.7) -> (56, 53.7)
  line L769 (56, 53.7) -> (56, 54.3)
  line L770 (56, 54.3) -> (52, 54.3)
  line L771 (52, 54.3) -> (52, 53.7)
  line L772 (53.7, 52) -> (54.3, 52)
  line L773 (54.3, 52) -> (54.3, 56)
  line L774 (54.3, 56) -> (53.7, 56)
  line L775 (53.7, 56) -> (53.7, 52)
  line L776 (52, 75.7) -> (56, 75.7)
  line L777 (56, 75.7) -> (56, 76.3)
  line L778 (56, 76.3) -> (52, 76.3)
  line L779 (52, 76.3) -> (52, 75.7)
  line L780 (53.7, 74) -> (54.3, 74)
  line L781 (54.3, 74) -> (54.3, 78)
  line L782 (54.3, 78) -> (53.7, 78)
  line L783 (53.7, 78) -> (53.7, 74)
  line L784 (74, 53.7) -> (78, 53.7)
  line L785 (78, 53.7) -> (78, 54.3)
  line L786 (78, 54.3) -> (74, 54.3)
  line L787 (74, 54.3) -> (74, 53.7)
  line L788 (75.7, 52) -> (76.3, 52)
  line L789 (76.3, 52) -> (76.3, 56)
  line L790 (76.3, 56) -> (75.7, 56)
  line L791 (75.7, 56) -> (75.7, 52)
  line L792 (74, 75.7) -> (78, 75.7)
  line L793 (78, 75.7) -> (78, 76.3)
  line L794 (78, 76.3) -> (74, 76.3)
  line L795 (74, 76.3) -> (74, 75.7)
  line L796 (75.7, 74) -> (76.3, 74)
  line L797 (76.3, 74) -> (76.3, 78)
  line L798 (76.3, 78) -> (75.7, 78)
  line L799 (75.7, 78) -> (75.7, 74)
extrude "scale_crosses (1)" cut sketch "scale_crosses" against normal blind 0.4 in component "drop_plate"
component "drop_plate" placed x (1, 0, 0) y (0, 1, 0) z (0, 0, 1) at (0, 0, 0)
equation "gf_fit_adjust = 0 mm" comment "Extra inward offset of the standard Gridfinity foot per side (0 = standard)"
equation "dp_units = 4" comment "Gridfinity units per side"
equation "dp_pitch = 32.5 mm" comment "Drop / cover pitch: 30.6 cover pocket + 1.9 locating post"
equation "dp_plate = 2.5 mm" comment "Plate thickness above the foot top"
equation "dp_cover = 29.65 mm" comment "Cover glass, caliper 14.11.26: average 29.65 (V2 assumed 30)"
equation "dp_clear = 0.3 mm" comment "Cover clearance per side (Lab 1: 0.4 moved freely, 0.2 jammed)"
equation "dp_gap = 0.6 mm" comment "Spacer pad height = resin layer thickness (3 layers at 0.2); measure each plate"
equation "dp_pad_w = 3 mm" comment "Spacer pad width"
equation "dp_pad_l = 6 mm" comment "Spacer pad length"
equation "dp_pad_c = 13.5 mm" comment "Spacer pad centre from the drop centre (pads under the cover edge midpoints)"
equation "dp_arm = 6 mm" comment "Stop arm length from the grid crossing along the cell boundary (reaches into the glass path)"
equation "dp_post_h = 2.4 mm" comment "Locating post height above the plate (cover top 1.8)"
equation "dp_mark = 11 mm" comment "Scale crosses at +-this from the drop centre (22 mm apart, under the cover corners)"
equation "dp_mark_len = 4 mm" comment "Scale cross arm length"
equation "groove_w = 0.6 mm" comment "Engraved line width (fill with black marker)"
equation "groove_d = 0.4 mm" comment "Engraved line depth"
equation "at_size = 24 mm" comment "AtomS3 outer size (caliper 13.11.26, M5Stack STL 24.0)"
equation "at_h = 12.9 mm" comment "AtomS3 height (caliper 13.11.26, M5Stack 12.9)"
equation "at_r = 3 mm" comment "AtomS3 plan corner radius (M5Stack STL)"
equation "at_wall = 1.6 mm" comment "Mock wall; open bottom clears the battery pins"
equation "at_roof = 3 mm" comment "Mock roof thickness at the top"
equation "at_win = 17.8 mm" comment "Screen opening at the top face (M5Stack STL)"
equation "at_win_r = 1.2 mm" comment "Screen opening corner radius (M5Stack STL)"
equation "at_win_in = 16.2 mm" comment "Screen opening below the 45 deg chamfer (M5Stack STL)"
equation "at_chamfer = 0.8 mm" comment "45 deg chamfer depth of the opening (M5Stack STL 0.79)"
equation "at_recess = 1.2 mm" comment "Screen surface below the top face (frame thickness in the M5Stack STL; >= real recess)"